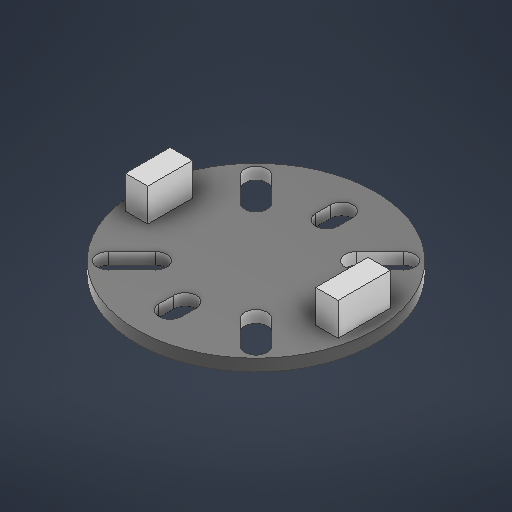
# Autodesk Inventor part: mt6701
Saved by Autodesk Inventor 2027.1 (Build 311270010, 270A)
## iProperties
Created: 2026-10-10
Part Number: mt6701
Material: Generic
Document SubType Name: Modeling
Designer: lucao
Density: 1 g/cm^3
Appearance: Default
Author: lucao
Autodesk Inventor part; units mm, degrees
ref_plane "YZ Plane" through (0, 0, 0) normal (1, 0, 0) x (0, 1, 0)
ref_plane "XZ Plane" through (0, 0, 0) normal (0, 1, 0) x (-1, 0, 0)
ref_plane "XY Plane" through (0, 0, 0) normal (0, 0, 1) x (1, 0, 0)
sketch "Sketch1" plane through (0, 0, 0) normal (0, 1, 0) x (-1, 0, 0)
  circle A0 centre (0, 0) radius 16
  dimension "d0" = 32
  constraints: 1 centre point, 1 coincident
  measures "d0" diameter of A0
extrude "Extrusion1" add sketch "Sketch1" along normal blind 1.6
sketch "Sketch2" plane through (0, 1.6, 0) normal (0, 1, 0) x (1, 0, 0)
  circle A0 centre (0, 0) radius 9.5 construction
  arc A1 (1.5, -9.5) -> (-1.5, -9.5) centre (0, -9.5) ccw
  arc A2 (-5.6569, -7.7782) -> (-7.7782, -5.6569) centre (-6.7175, -6.7175) ccw
  line L0 (0, 0) -> (-6.7175, -6.7175) construction
  line L1 (0, 0) -> (0, -9.5) construction
  arc A3 (-1.5, -11.5) -> (1.5, -11.5) centre (0, -11.5) ccw
  line L2 (1.5, -9.5) -> (1.5, -11.5)
  line L3 (-1.5, -11.5) -> (-1.5, -9.5)
  line L4 (-6.7175, -6.7175) -> (-9.8995, -9.8995) construction
  arc A4 (-10.9602, -8.8388) -> (-8.8388, -10.9602) centre (-9.8995, -9.8995) ccw
  line L5 (-8.8388, -10.9602) -> (-5.6569, -7.7782)
  line L6 (-10.9602, -8.8388) -> (-7.7782, -5.6569)
  line L7 (0, 0) -> (-9.5, 0) construction
  arc A5 (7.7782, -5.6569) -> (5.6569, -7.7782) centre (6.7175, -6.7175) ccw
  arc A6 (8.8388, -10.9602) -> (10.9602, -8.8388) centre (9.8995, -9.8995) ccw
  line L8 (8.8388, -10.9602) -> (5.6569, -7.7782)
  line L9 (10.9602, -8.8388) -> (7.7782, -5.6569)
  arc A7 (-1.5, 9.5) -> (1.5, 9.5) centre (0, 9.5) ccw
  arc A8 (-7.7782, 5.6569) -> (-5.6569, 7.7782) centre (-6.7175, 6.7175) ccw
  arc A9 (1.5, 11.5) -> (-1.5, 11.5) centre (0, 11.5) ccw
  line L10 (1.5, 9.5) -> (1.5, 11.5)
  line L11 (-1.5, 11.5) -> (-1.5, 9.5)
  arc A10 (-8.8388, 10.9602) -> (-10.9602, 8.8388) centre (-9.8995, 9.8995) ccw
  line L12 (-8.8388, 10.9602) -> (-5.6569, 7.7782)
  line L13 (-10.9602, 8.8388) -> (-7.7782, 5.6569)
  arc A11 (10.9602, 8.8388) -> (8.8388, 10.9602) centre (9.8995, 9.8995) ccw
  line L14 (8.8388, 10.9602) -> (5.6569, 7.7782)
  line L15 (10.9602, 8.8388) -> (7.7782, 5.6569)
  arc A12 (5.6569, 7.7782) -> (7.7782, 5.6569) centre (6.7175, 6.7175) ccw
  dimension "d3" = 19
  dimension "d4" = 3
  dimension "d8" = 3
  dimension "d10" = 45
  dimension "d11" = 3
  dimension "d12" = 11.5
  dimension "d13" = 4.5
  dimension "d14" = 3
  constraints: 32 end point, 27 point on circle, 24 symmetric about line, 13 centre point, 7 tangent, 2 vertical, 1 coincident, 1 perpendicular, 1 point on line, 1 vertical alignment, 8 other
  measures "d3" diameter of A0
  measures "d4" diameter of A1
  measures "d8" diameter of A2
  measures "d10" angle of L1 L0
  measures "d11" diameter of A3
  measures "d12" distance of point (0, 0) A3.centre
  measures "d13" distance of L4.end L0.end
  measures "d14" diameter of A4
extrude "Extrusion2" cut sketch "Sketch2" against normal through all
sketch "Sketch3" plane through (0, 1.6, 0) normal (0, 1, 0) x (1, 0, 0)
  line L0 (-11.5, -3) -> (-14.5, -3)
  line L1 (-14.5, -3) -> (-14.5, 3)
  line L2 (-14.5, 3) -> (-11.5, 3)
  line L3 (-11.5, 3) -> (-11.5, -3)
  line L4 (-11.5, -3) -> (-14.5, 3) construction
  line L5 (-14.5, -3) -> (-11.5, 3) construction
  line L6 (14.5, -3.5) -> (11.5, -3.5)
  line L7 (11.5, -3.5) -> (11.5, 3.5)
  line L8 (11.5, 3.5) -> (14.5, 3.5)
  line L9 (14.5, 3.5) -> (14.5, -3.5)
  line L10 (14.5, -3.5) -> (11.5, 3.5) construction
  line L11 (11.5, -3.5) -> (14.5, 3.5) construction
  point P0 (0, 0)
  point P1 (-13, 0)
  point P2 (13, 0)
  dimension "d17" = 29
  dimension "d18" = 6
  dimension "d19" = 3
  dimension "d20" = 14.5
  dimension "d21" = 3
  dimension "d22" = 7
  constraints: 24 end point, 4 midpoint, 4 parallel, 2 horizontal, 2 horizontal alignment, 2 perpendicular
  measures "d17" distance between parallel lines of L1 L9
  measures "d18" distance of L0.end L1.end
  measures "d19" distance of L1.end L2.end
  measures "d20" distance from line of point (0, 0) L1
  measures "d21" distance of L7.end L8.end
  measures "d22" distance of L6.end L7.end
extrude "Extrusion3" add sketch "Sketch3" along normal blind 4.4
sketch "Sketch4" plane through (0, 0, 0) normal (0, -1, 0) x (1, 0, 0)
  line L0 (2, 1.5) -> (-2, 1.5)
  line L1 (-2, 1.5) -> (-2, -1.5)
  line L2 (-2, -1.5) -> (2, -1.5)
  line L3 (2, -1.5) -> (2, 1.5)
  line L4 (2, 1.5) -> (-2, -1.5) construction
  line L5 (-2, 1.5) -> (2, -1.5) construction
  point P0 (0, 0)
  dimension "d25" = 4
  dimension "d26" = 3
  constraints: 12 end point, 2 midpoint, 2 parallel, 1 horizontal, 1 perpendicular
  measures "d25" distance of L2.end L1.end
  measures "d26" distance of L1.end L0.end
extrude "Extrusion4" add sketch "Sketch4" along normal blind 1.7
equation "\"d20\" = 0.5 * d17"
body "Solid1"
